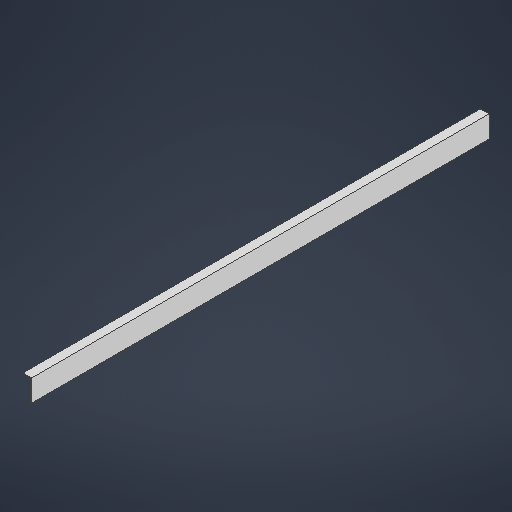
# Autodesk Inventor part: side_bar
Saved by Autodesk Inventor 2027 (Build 310192060, 192F)
## iProperties
Created: 2026-10-18
Part Number: side_bar
Material: Générique
Document SubType Name: Modeling
Designer: strei
Density: 1 g/cm^3
Appearance: Par défaut
Author: strei
Autodesk Inventor part; units mm, degrees
ref_plane "YZ Plane" through (0, 0, 0) normal (1, 0, 0) x (0, 1, 0)
ref_plane "XZ Plane" through (0, 0, 0) normal (0, 1, 0) x (-1, 0, 0)
ref_plane "XY Plane" through (0, 0, 0) normal (0, 0, 1) x (1, 0, 0)
sketch "Esquisse1" plane through (0, 0, 0) normal (0, 0, 1) x (1, 0, 0)
  line L0 (0, 0) -> (-18, 0)
  line L1 (-18, 0) -> (-18, 2)
  line L2 (-18, 2) -> (2, 2)
  line L3 (2, 2) -> (2, -48)
  line L4 (2, -48) -> (0, -48)
  line L5 (0, -48) -> (0, -49.2101)
  line L6 (0, -49.2101) -> (0, 0)
  dimension "d0" = 2
  dimension "d1" = 2
  dimension "d2" = 50
  dimension "d3" = 20
  constraints: 14 end point, 4 perpendicular, 1 collinear, 1 horizontal, 1 vertical
  measures "d0" distance of L0.end L1.end
  measures "d1" distance of L3.end L4.end
  measures "d2" distance of L2.end L3.end
  measures "d3" distance of L1.end L2.end
extrude "Extrusion1" add sketch "Esquisse1" along normal mid plane 1050
equation "\"d1\" = d0"
